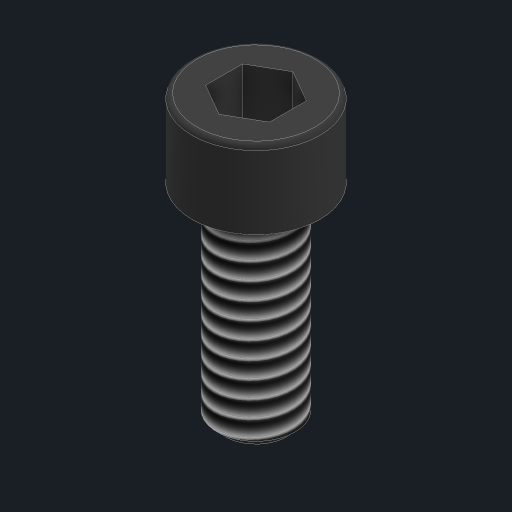
# Autodesk Inventor part: Parafuso allen cabeça cilíndrica ASME B18.3 UNC 10 x 0,5 pol
Saved by Autodesk Inventor 2024.3 (Build 283343000, 343)
## iProperties
Created: 2025-01-16
Part Number: Parafuso allen cabeça cilíndrica ASME B18.3 UNC 10 x 0,5 pol
Material: Aço, carbono
Document SubType Name: Modeling
Designer: Cliente
Density: 7.85 g/cm^3
Appearance: Semipolido
Mass: 3.21656 g
Surface Area: 4.57152 cm^2
Volume: 0.409752 cm^3
Author: Cliente
Autodesk Inventor part; units mm, degrees
ref_plane "YZ Plane" through (0, 0, 0) normal (1, 0, 0) x (0, 1, 0)
ref_plane "XZ Plane" through (0, 0, 0) normal (0, 1, 0) x (-1, 0, 0)
ref_plane "XY Plane" through (0, 0, 0) normal (0, 0, 1) x (1, 0, 0)
sketch "Esboço1" plane through (0, 0, 0) normal (0, 1, 0) x (-1, 0, 0)
  circle A0 centre (0, 0) radius 2.413
  dimension "d0" = 4.826
  constraints: 1 centre point, 1 coincident
  measures "d0" diameter of A0
extrude "Extrusão1" add sketch "Esboço1" along normal blind 12.7
sketch "Esboço2" plane through (0, 12.7, 0) normal (0, 1, 0) x (1, 0, 0)
  circle A0 centre (0, 0) radius 3.96
  circle A1 centre (0, 0) radius 2.413 projected
  line L0 (0, 2.2914) -> (1.9844, 1.1457)
  line L1 (1.9844, 1.1457) -> (1.9844, -1.1457)
  line L2 (1.9844, -1.1457) -> (0, -2.2914)
  line L3 (0, -2.2914) -> (-1.9844, -1.1457)
  line L4 (-1.9844, -1.1457) -> (-1.9844, 1.1457)
  line L5 (-1.9844, 1.1457) -> (0, 2.2914)
  dimension "d3" = 7.92
  dimension "d9" = 3.9688
  constraints: 12 end point, 2 coincident, 1 centre point, 1 vertical alignment, 13 other
  measures "d3" diameter of A0
  measures "d9" distance between parallel lines of L1 L4
extrude "Extrusão2" add sketch "Esboço2" along normal blind 4.82 contours A0 | A1
chamfer "Chanfro1" distance 1.205 angle 45 6 edges at (-0.9922, 12.7, -1.7185) (-1.9844, 12.7, 0) (-0.9922, 12.7, 1.7185) (0.9922, 12.7, 1.7185) (1.9844, 12.7, 0) (0.9922, 12.7, -1.7185)
fillet "Arredondamento1" radius 0.05 1 edges at (2.413, 12.7, 0)
fillet "Arredondamento2" radius 0.3 1 edges at (-3.96, 17.52, 0)
thread "Rosca1" size "10-24 UNC" class "2A" standard "ANSI Unified Screw Threads" full length
chamfer "Chanfro2" distance 0.5 angle 45 1 edges at (2.413, 0, 0)
